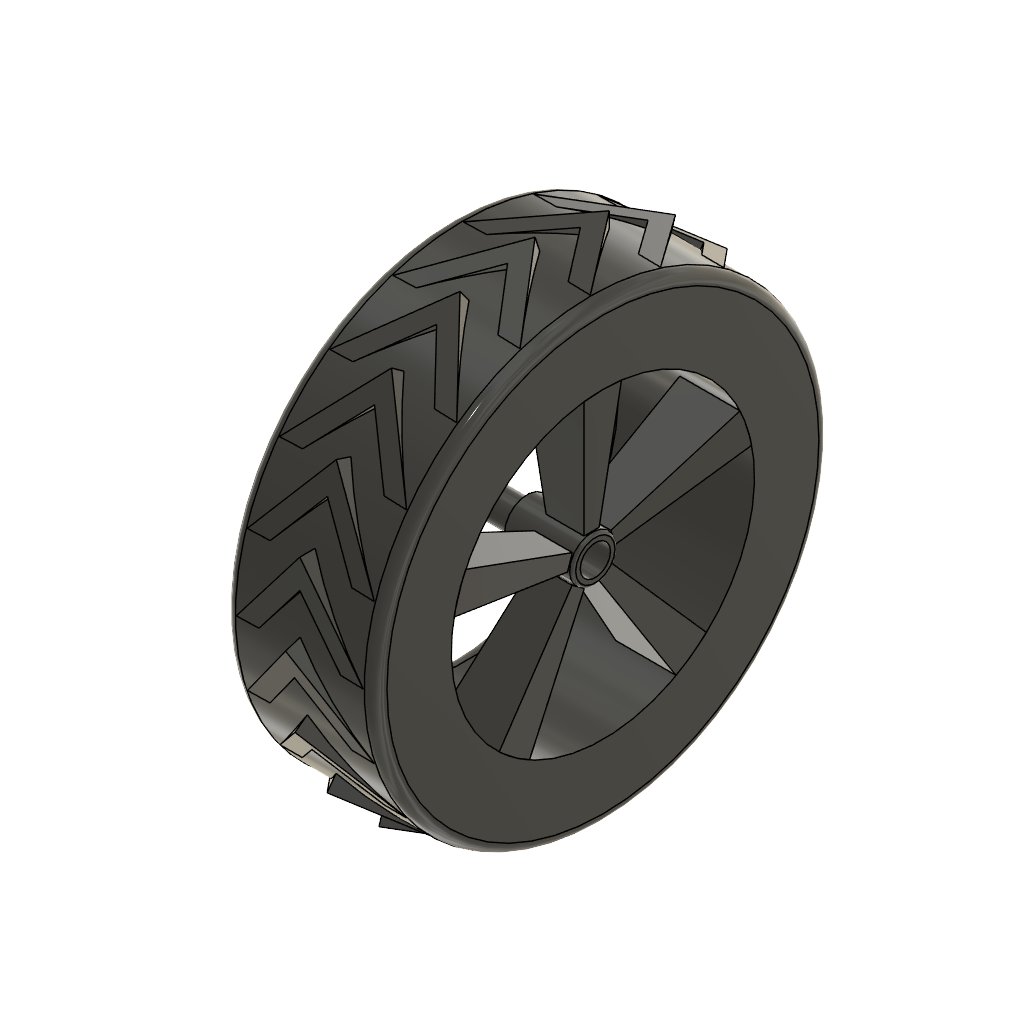
roue_desherbeur (Autodesk Fusion 360 design; units mm, degrees)
part number: 2026-11-26-21-45-35-368
Autodesk Fusion 360 part; units mm, degrees
sketch "Esquisse3" plane through (0, 0, 0) normal (0, 1, 0) x (1, 0, 0)
  line L0 (-30, -30) -> (30, -30) construction
  line L1 (0, -30) -> (-10, -30)
  line L2 (0, -30) -> (10, -30)
  line L3 (-10, -30) -> (-10, -20)
  line L4 (-10, -20) -> (10, -20)
  line L5 (10, -20) -> (10, -30)
  dimension "d8" = 30
  dimension "d11" = 10
  dimension "d12" = 10
  dimension "d13" = 10
  constraint horizontal L0
  constraint midpoint L0 L1.start
  constraint parallel L0 L1
  constraint parallel L0 L2
  constraint perpendicular L1 L3
  constraint perpendicular L3 L4
  measures "d8" distance of origin L0
  measures "d11" distance of L1.start L1.end
  measures "d12" distance of L1.start L2.end
  measures "d13" distance of L1.end L3.end
revolve "Révolution1" add sketch "Esquisse3" angle 360 about axis through (1.75, 0, 0) along (1, 0, 0) makes body 1
ref_plane "Plan de construction1" through (2.2965, 0, 30) normal (0, 0, 1) x (0, -1, 0)
sketch "Esquisse4" plane through (0, 0, 30) normal (0, 0, 1) x (1, 0, 0)
  line L0 (-8.3845, -0.0572) -> (0, 10.8426)
  line L1 (0, 7.0267) -> (-5.3856, 0.0253)
  line L2 (-5.3856, 0.0253) -> (-8.3845, -0.0572)
  line L3 (0, 1.75) -> (0, 22.5)
  line L4 (0, 7.0267) -> (5.3856, 0.0253)
  line L5 (5.3856, 0.0253) -> (8.3845, -0.0572)
  line L6 (8.3845, -0.0572) -> (0, 10.8426)
  dimension "d18" = 3
  constraint parallel L0 L1
  constraint symmetric L0.start L3 L5.end
  constraint symmetric L1.end L3 L4.end
  measures "d18" distance of L0.start L1.end
extrude "Extrusion3" add sketch "Esquisse4" along normal up to surface end surface at (-3.3333, 1.4954, 29.9627) on bodies 1 bodies 1
pattern_circular "Réseau C1" count 20 over 360 about axis through (10, 0, 0) along (-1, 0, 0) of "Extrusion3"
fillet "Congé1" radius 1.5 2 edges at (10, -10.8485, -27.9698) (-10, -10.8485, -27.9698) on bodies 1
sketch "Esquisse5" plane through (0, 0, 0) normal (1, 0, 0) x (0, 1, 0)
  circle A0 centre (0, 0) radius 1.5
  circle A1 centre (0, 0) radius 2
  dimension "d26" = 3
  dimension "d27" = 4
  constraint coincident A0.centre A1.centre
  constraint concentric A0 A1
  measures "d26" diameter of A0
  measures "d27" diameter of A1
extrude "Extrusion4" add sketch "Esquisse5" against normal blind 10 separate body contours A0 | A1 makes body 2
extrude "Extrusion5" add sketch "Esquisse5" against normal blind 14 bodies 2
sketch "Esquisse6" plane through (0, 0, 0) normal (1, 0, 0) x (0, 1, 0)
  circle A0 centre (0, 0) radius 2
  circle A1 centre (0, 0) radius 3
  dimension "d32" = 6
  constraint coincident A0.centre A1.centre
  measures "d32" diameter of A1
extrude "Extrusion6" add sketch "Esquisse6" along normal blind 9 contours A0 | A1 bodies 2
sketch "Esquisse7" plane through (9, 0, 0) normal (1, 0, 0) x (0, 1, 0)
  circle A0 centre (0, 0) radius 3
  circle A1 centre (0, 0) radius 2
  constraint coincident A0.centre A1.centre
extrude "Extrusion7" cut sketch "Esquisse7" against normal blind 5 contours A1 bodies 2
ref_plane "Plan de construction2" through (3.7401, 0, 3) normal (0, 0, 1) x (0, 1, 0)
sketch "Esquisse8" plane through (0, 0, 3) normal (0, 0, 1) x (1, 0, 0)
  line L0 (8.5, -1) -> (3.5, -1)
  line L1 (3.5, -1) -> (3.5, 1)
  line L2 (3.5, 1) -> (8.5, 1)
  line L3 (8.5, 1) -> (8.5, -1)
  line L4 (8.5, -1) -> (3.5, 1) construction
  line L5 (3.5, -1) -> (8.5, 1) construction
  point P0 (6, 0)
  dimension "d39" = 5
  dimension "d40" = 2
  constraint horizontal L0
  constraint perpendicular L0 L1
  constraint parallel L0 L2
  constraint parallel L1 L3
  constraint coincident L4 P0
  constraint coincident L5 P0
  measures "d39" distance of L1.end L2.end
  measures "d40" distance of L0.end L1.end
extrude "Extrusion8" add sketch "Esquisse8" along normal up to surface draft 5 end surface at (-3.3333, 0.9969, 19.9751) on bodies 1 bodies 1 2
pattern_circular "Réseau C2" count 5 over 360 about axis through (9, 0, 0) along (1, 0, 0) of "Extrusion8"
fillet "Congé2" radius 0.4 1 edges at (9, -2.797, -1.0848) on bodies 1
fillet "Congé3" radius 2 1 edges at (-10, -7.2323, -18.6465) on bodies 1
